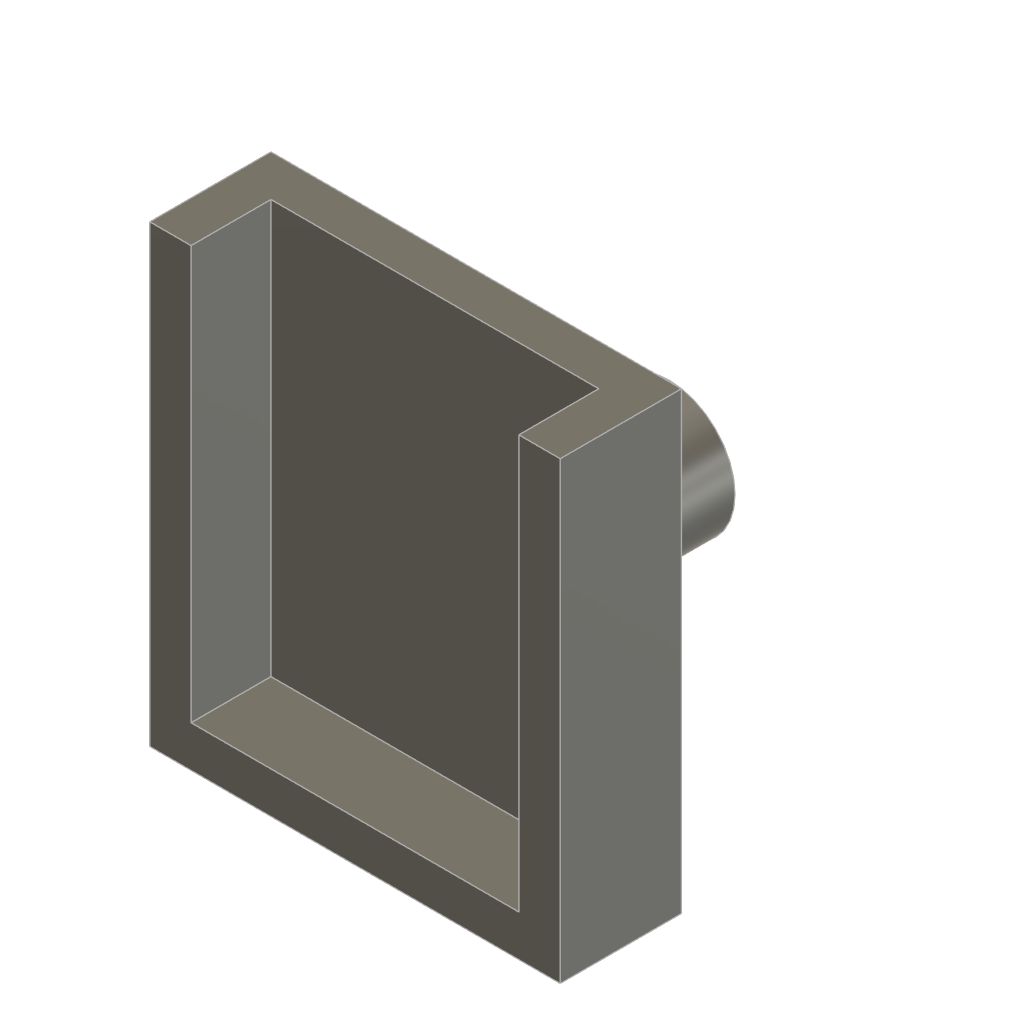
MicroServoHelper (Autodesk Fusion 360 design; units mm, degrees)
part number: 2026-07-20-19-57-06-824
Autodesk Fusion 360 part; units mm, degrees
sketch "Sketch1" plane through (0, 0, 0) normal (0, 1, 0) x (1, 0, 0)
  line L0 (7.6, -2.25) -> (-7.6, -2.25)
  line L1 (-7.6, -2.25) -> (-7.6, 2.25)
  line L2 (-7.6, 2.25) -> (7.6, 2.25)
  line L3 (7.6, 2.25) -> (7.6, -2.25)
  line L4 (7.6, -2.25) -> (-7.6, 2.25) construction
  line L5 (-7.6, -2.25) -> (7.6, 2.25) construction
  dimension "d1" = 15.2
  dimension "d2" = 4.5
  constraint horizontal L0
  constraint perpendicular L0 L1
  constraint parallel L0 L2
  constraint parallel L1 L3
  constraint coincident L4 origin
  constraint coincident L5 origin
  measures "d1" distance of L1.end L2.end
  measures "d2" distance of L0.end L1.end
extrude "Extrude1" add sketch "Sketch1" along normal blind 1.5
sketch "Sketch2" plane through (0, 1.5, 0) normal (0, 1, 0) x (-1, 0, 0)
  line L0 (-7.6, -2.25) -> (7.6, -2.25)
  line L1 (7.6, -2.25) -> (7.6, 2.25)
  line L2 (7.6, 2.25) -> (-7.6, 2.25)
  line L3 (-7.6, 2.25) -> (-7.6, -2.25)
  line L4 (-6.1, -0.75) -> (6.1, -0.75)
  line L5 (6.1, 2.25) -> (6.1, -0.75)
  line L6 (-6.1, 2.25) -> (-6.1, -0.75)
  dimension "d5" = 1.5
  dimension "d6" = 1.5
  constraint coincident L2 L5.start
  constraint perpendicular L1 L4
  constraint perpendicular L4 L5
  constraint perpendicular L4 L6
  measures "d5" distance of L2.end L6.start
  measures "d6" distance of L1.end L5.start
extrude "Extrude2" add sketch "Sketch2" along normal blind 15 contours L0 L1 L2 L3 L4 L5 L6
sketch "Sketch3" plane through (0, 0, -0.75) normal (0, 0, 1) x (1, 0, 0)
  line L0 (-6.1, 1.5) -> (6.1, 1.5)
  line L1 (6.1, 1.5) -> (6.1, 16.5)
  line L2 (6.1, 16.5) -> (-6.1, 16.5)
  line L3 (-6.1, 16.5) -> (-6.1, 1.5)
  circle A0 centre (0, 7.15) radius 2.45
  dimension "d12" = 4.9
  measures "d12" diameter of A0
extrude "Extrude3" add sketch "Sketch3" against normal blind 8.5 contours A0
extrude "Extrude4" add 1 faces at (-6.1, 6.5, 1.25) along direction (1, 0, 0) blind 0.15
extrude "Extrude5" add 1 faces at (6.1, 6.5, 1.25) along direction (-1, 0, 0) blind 0.15
extrude "Extrude6" cut 1 faces at (-7.6, 5.5, 0.75) along direction (1, 0, 0) blind 0.15
extrude "Extrude7" cut 1 faces at (7.6, 5.5, -0.75) along direction (-1, 0, 0) blind 0.15
extrude "Extrude8" cut 1 faces at (-6.95, 6, 2.25) along direction (0, 0, -1) blind 0.1
move_face "OffsetFaces1" offset -0.1 1 faces at (2.4378, 6.9061, -4.5833)
move_face "OffsetFaces2" offset 0.05 1 faces at (2.3383, 6.916, -4.5833)
